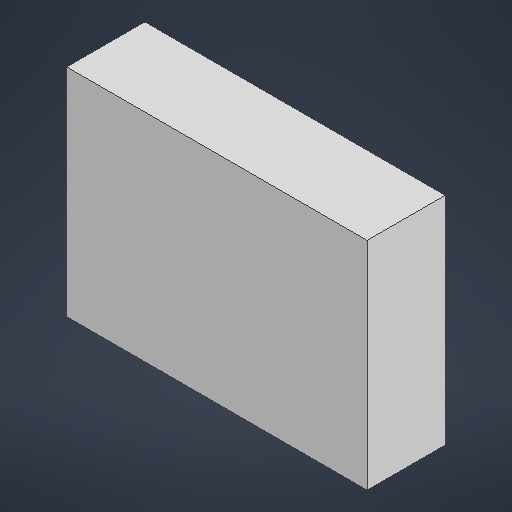
# Autodesk Inventor part: batterys
Saved by Autodesk Inventor 2027 (Build 310192000, 192)
## iProperties
Created: 2026-11-19
Part Number: batterys
Material: Generic
Document SubType Name: Modeling
Designer: user
Density: 1 g/cm^3
Appearance: Default
Author: user
Autodesk Inventor part; units mm, degrees
ref_plane "YZ Plane" through (0, 0, 0) normal (1, 0, 0) x (0, 1, 0)
ref_plane "XZ Plane" through (0, 0, 0) normal (0, 1, 0) x (-1, 0, 0)
ref_plane "XY Plane" through (0, 0, 0) normal (0, 0, 1) x (1, 0, 0)
sketch "Sketch1" plane through (0, 0, 0) normal (0, 0, 1) x (1, 0, 0)
  line L0 (-12.5, 9) -> (12.5, 9)
  line L1 (12.5, 9) -> (12.5, -9)
  line L2 (12.5, -9) -> (-12.5, -9)
  line L3 (-12.5, -9) -> (-12.5, 9)
  line L4 (-12.5, 9) -> (12.5, -9) construction
  line L5 (12.5, 9) -> (-12.5, -9) construction
  point P0 (0, 0)
  dimension "d0" = 25
  dimension "d1" = 18
  constraints: 12 end point, 2 midpoint, 2 parallel, 1 horizontal, 1 perpendicular
  measures "d0" distance of L1.end L2.end
  measures "d1" distance of L0.end L1.end
extrude "Extrusion1" add sketch "Sketch1" along normal blind 6.5
body "Solid1"
